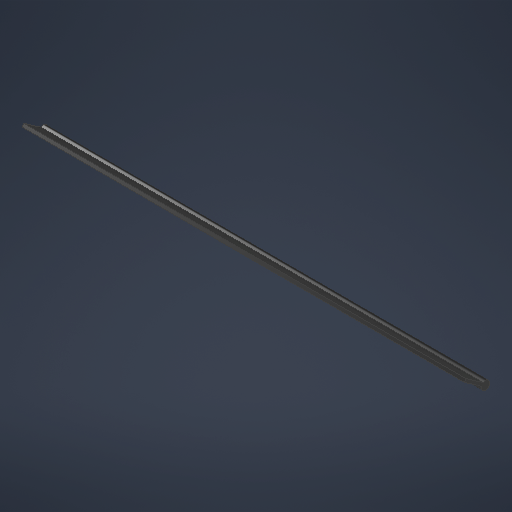
# Autodesk Inventor part: Rubber blade
Saved by Autodesk Inventor 2026.2 (Build 302298010, 298A)
## iProperties
Created: 2026-07-16
Part Number: Rubber blade
Material: Generic
Document SubType Name: Modeling
Designer: grady
Density: 1 g/cm^3
Appearance: Default
Author: grady
Autodesk Inventor part; units mm, degrees
ref_plane "YZ Plane" through (0, 0, 0) normal (1, 0, 0) x (0, 1, 0)
ref_plane "XZ Plane" through (0, 0, 0) normal (0, 1, 0) x (-1, 0, 0)
ref_plane "XY Plane" through (0, 0, 0) normal (0, 0, 1) x (1, 0, 0)
sketch "Sketch3" plane through (0, 0, 0) normal (1, 0, 0) x (0, 1, 0)
  arc A0 (0.9285, 3.3746) -> (2.8535, 2.0267) centre (0, 0) ccw
  line L0 (0, 0) -> (20, 0) construction
  line L1 (11.4715, 16.383) -> (12.434, 15.7091)
  line L2 (12.434, 15.7091) -> (10.509, 17.057)
  line L3 (10.509, 17.057) -> (0.9285, 3.3746)
  line L4 (12.434, 15.7091) -> (2.8535, 2.0267)
  dimension "d8" = 7
  dimension "d9" = 20
  dimension "d11" = 1.175
  dimension "d12" = 2.35
  constraints: 10 end point, 2 point on circle, 1 centre point, 1 coincident, 1 horizontal, 1 parallel, 1 point on line
  measures "d8" diameter of A0
  measures "d9" distance of L0.start L1.start
  measures "d11" distance of L1.start L1.end
  measures "d12" distance of L1.end L2.end
extrude "Extrusion3" add sketch "Sketch3" along normal blind 355
body "Solid2"
